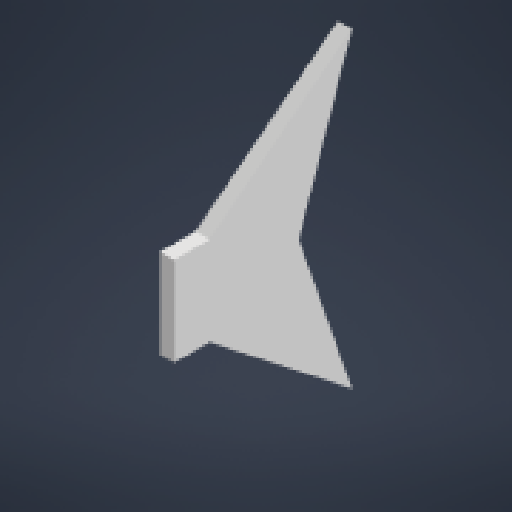
# Autodesk Inventor part: tail
Saved by Autodesk Inventor 2027 (Build 310192060, 192F)
## iProperties
Created: 2026-04-15
Part Number: tail
Material: Generic
Document SubType Name: Modeling
Designer: thita
Density: 1 g/cm^3
Appearance: Default
Author: thita
Autodesk Inventor part; units mm, degrees
ref_plane "YZ Plane" through (0, 0, 0) normal (1, 0, 0) x (0, 1, 0)
ref_plane "XZ Plane" through (0, 0, 0) normal (0, 1, 0) x (-1, 0, 0)
ref_plane "XY Plane" through (0, 0, 0) normal (0, 0, 1) x (1, 0, 0)
sketch "Sketch1" plane through (0, 0, 0) normal (0, 0, 1) x (1, 0, 0)
  line L0 (4, -25) -> (4, 25)
  line L1 (4, 25) -> (-4, 25)
  line L2 (-4, 25) -> (-4, -25)
  line L3 (-4, -25) -> (4, -25)
  line L4 (4, -25) -> (-4, 25) construction
  line L5 (4, 25) -> (-4, -25) construction
  point P0 (0, 0)
  dimension "d0" = 50
  dimension "d1" = 8
  constraints: 12 end point, 2 midpoint, 2 parallel, 1 perpendicular, 1 vertical
  measures "d0" distance of L0.start L0.end
  measures "d1" distance of L1.end L0.end
extrude "Extrusion1" add sketch "Sketch1" against normal blind 20
sketch "Sketch2" plane through (4, -25, 0) normal (1, 0, 0) x (0, 0, -1)
  line L0 (20, 50) -> (20, 0) projected
  line L1 (100, 112.5) -> (100, -62.5)
  line L2 (0, 50) -> (20, 50) projected
  line L3 (20, 50) -> (100, 112.5)
  line L4 (100, -62.5) -> (20, 0)
  line L5 (70, 25) -> (100, 112.5)
  line L6 (70, 25) -> (100, -62.5)
  point P0 (0, 25)
  dimension "d12" = 175
  constraints: 10 end point, 1 vertical
  measures "d12" distance of L1.start L1.end
extrude "Extrusion2" add sketch "Sketch2" against normal up to surface (8 mm away) contours L3 L5 L6 L4 L0
body "Solid1"
